Top Lid Link native (Autodesk Fusion 360 design; units mm, degrees)
part number: 2026-10-13-21-21-50-831
Autodesk Fusion 360 part; units mm, degrees
ref_plane "WorkPlane1" through (-15.435, 0, 0) normal (1, 0, 0) x (0, 1, 0)
sketch "Profile" plane through (-15.435, 0, 0) normal (1, 0, 0) x (0, 0, -1)
  line L0 (-3.7804, 19.9283) -> (-36.5631, 15.588)
  arc A0 (-36.5631, 15.588) -> (-36.0381, 11.6226) centre (-36.3006, 13.6053) ccw
  line L1 (-36.0381, 11.6226) -> (-4.0101, 15.8629)
  arc A1 (-1.5456, 15.5677) -> (-4.0101, 15.8629) centre (-3.3539, 10.9069) ccw
  line L2 (-1.5456, 15.5677) -> (2.8956, 13.8446)
  arc A2 (2.8956, 13.8446) -> (4.261, 17.6043) centre (3.577, 15.7249) ccw
  line L3 (4.261, 17.6043) -> (-1.4143, 19.67)
  arc A3 (-1.4143, 19.67) -> (-3.7804, 19.9283) centre (-3.1242, 14.9722) ccw
  dimension "d13" = 2
  dimension "d14" = 4.9993
  dimension "d15" = 36.3006
  dimension "d16" = 13.6053
  dimension "d17" = 3.3539
  dimension "d18" = 10.9069
  dimension "d19" = 3.577
  dimension "d20" = 15.7249
  dimension "d21" = 3.1242
  dimension "d22" = 14.9722
  dimension "d23" = 1.5456
  constraint tangent L0 A3
  constraint tangent L0 A0
  constraint tangent A0 L1
  constraint tangent L1 A1
  constraint tangent A1 L2
  constraint tangent A2 L3
  constraint tangent L3 A3
  constraint equal A0 A2
  constraint equal A1 A3
  measures "d13" radius of A0
  measures "d14" radius of A1
  measures "d15" horizontal distance of origin A0.centre
  measures "d16" vertical distance of origin A0.centre
  measures "d17" horizontal distance of origin A1.centre
  measures "d18" vertical distance of origin A1.centre
  measures "d19" horizontal distance of origin A2.centre
  measures "d20" vertical distance of origin A2.centre
  measures "d21" horizontal distance of origin A3.centre
  measures "d22" vertical distance of origin A3.centre
  measures "d23" horizontal distance of origin A1.start
extrude "Profile (1)" add sketch "Profile" along normal mid plane 2
ref_plane "WorkPlane2" through (-15.435, 0, 0) normal (1, 0, 0) x (0, 1, 0)
sketch "Hole 1" plane through (-15.435, 0, 0) normal (1, 0, 0) x (0, 0, -1)
  circle A0 centre (-36.3006, 13.6053) radius 1.25
  dimension "d24" = 2.5
  dimension "d25" = 36.3006
  dimension "d26" = 13.6053
  measures "d24" diameter of A0
  measures "d25" horizontal distance of origin A0.centre
  measures "d26" vertical distance of origin A0.centre
extrude "Hole 1 (1)" cut sketch "Hole 1" along normal mid plane 2
ref_plane "WorkPlane3" through (-15.435, 0, 0) normal (1, 0, 0) x (0, 1, 0)
sketch "Hole 2" plane through (-15.435, 0, 0) normal (1, 0, 0) x (0, 0, -1)
  circle A0 centre (3.577, 15.7249) radius 1.2499
  dimension "d27" = 2.4999
  dimension "d28" = 3.577
  dimension "d29" = 15.7249
  measures "d27" diameter of A0
  measures "d28" horizontal distance of origin A0.centre
  measures "d29" vertical distance of origin A0.centre
extrude "Hole 2 (1)" cut sketch "Hole 2" along normal mid plane 2
named bodies: "Top Lid Link native"
